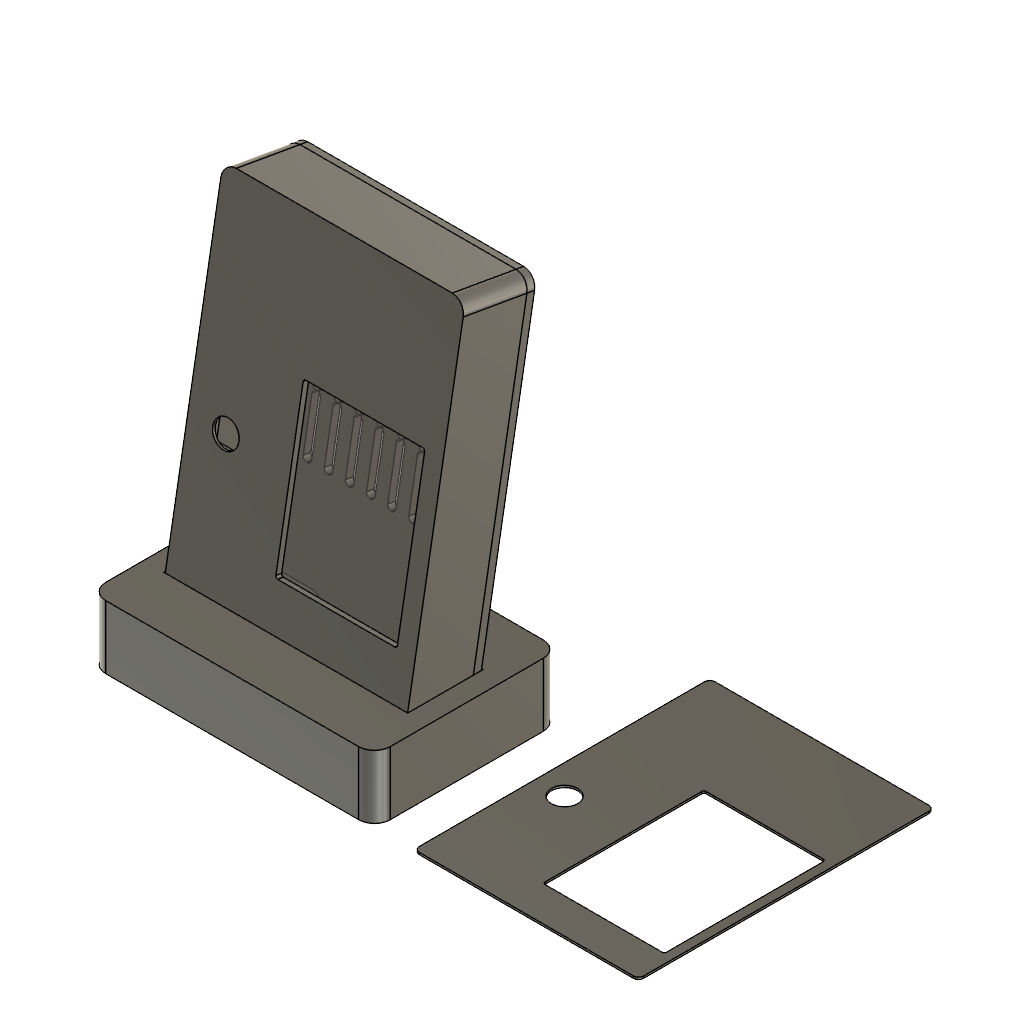
smart-picture-frame (Autodesk Fusion 360 design; units mm, degrees)
Autodesk Fusion 360 part; units mm, degrees
sketch "Shell outline" plane through (0, 0, 0) normal (0, 0, 1) x (1, 0, 0) in component "Front shell"
  line L0 (5, 0) -> (86.8, 0)
  arc A0 (86.8, 0) -> (91.8, 5) centre (86.8, 5) ccw
  line L1 (91.8, 5) -> (91.8, 134.3)
  arc A1 (91.8, 134.3) -> (86.8, 139.3) centre (86.8, 134.3) ccw
  line L2 (86.8, 139.3) -> (5, 139.3)
  arc A2 (5, 139.3) -> (0, 134.3) centre (5, 134.3) ccw
  line L3 (0, 134.3) -> (0, 5)
  arc A3 (0, 5) -> (5, 0) centre (5, 5) ccw
extrude "Shell outline (1)" add sketch "Shell outline" along normal blind 24.5 from surface at 3 makes body 1 in component "Front shell"
sketch "Cavity (leaves screw bosses)" plane through (0, 0, 0) normal (0, 0, 1) x (1, 0, 0) in component "Front shell"
  line L0 (5, 2.4) -> (86.8, 2.4)
  arc A0 (86.8, 2.4) -> (89.4, 5) centre (86.8, 5) ccw
  line L1 (89.4, 5) -> (89.4, 134.3)
  arc A1 (89.4, 134.3) -> (86.8, 136.9) centre (86.8, 134.3) ccw
  line L2 (86.8, 136.9) -> (5, 136.9)
  arc A2 (5, 136.9) -> (2.4, 134.3) centre (5, 134.3) ccw
  line L3 (2.4, 134.3) -> (2.4, 5)
  arc A3 (2.4, 5) -> (5, 2.4) centre (5, 5) ccw
  circle A4 centre (40.4, 5.4) radius 4
  circle A5 centre (86.4, 5.4) radius 4
  circle A6 centre (5.4, 133.9) radius 4
  circle A7 centre (86.4, 133.9) radius 4
extrude "Cavity (leaves screw bosses) (1)" cut sketch "Cavity (leaves screw bosses)" along normal blind 21.52 from surface at 2.98 contours L0 L1 L2 L3 A3 A4 A5 A6 A7 bodies 1 in component "Front shell"
sketch "Screen window" plane through (0, 0, 0) normal (0, 0, 1) x (1, 0, 0) in component "Front shell"
  line L0 (39.7, 29.7) -> (84.1, 29.7)
  arc A0 (84.1, 29.7) -> (84.9, 30.5) centre (84.1, 30.5) ccw
  line L1 (84.9, 30.5) -> (84.9, 89.9)
  arc A1 (84.9, 89.9) -> (84.1, 90.7) centre (84.1, 89.9) ccw
  line L2 (84.1, 90.7) -> (39.7, 90.7)
  arc A2 (39.7, 90.7) -> (38.9, 89.9) centre (39.7, 89.9) ccw
  line L3 (38.9, 89.9) -> (38.9, 30.5)
  arc A3 (38.9, 30.5) -> (39.7, 29.7) centre (39.7, 30.5) ccw
extrude "Screen window (1)" cut sketch "Screen window" along normal blind 3.04 from surface at 24.48 bodies 1 in component "Front shell"
sketch "Window inside relief" plane through (0, 0, 0) normal (0, 0, 1) x (1, 0, 0) in component "Front shell"
  line L0 (38.7, 28.7) -> (85.1, 28.7)
  arc A0 (85.1, 28.7) -> (85.9, 29.5) centre (85.1, 29.5) ccw
  line L1 (85.9, 29.5) -> (85.9, 90.9)
  arc A1 (85.9, 90.9) -> (85.1, 91.7) centre (85.1, 90.9) ccw
  line L2 (85.1, 91.7) -> (38.7, 91.7)
  arc A2 (38.7, 91.7) -> (37.9, 90.9) centre (38.7, 90.9) ccw
  line L3 (37.9, 90.9) -> (37.9, 29.5)
  arc A3 (37.9, 29.5) -> (38.7, 28.7) centre (38.7, 29.5) ccw
extrude "Window inside relief (1)" cut sketch "Window inside relief" along normal blind 0.8 from surface at 24.5 bodies 1 in component "Front shell"
sketch "Camera hole" plane through (0, 0, 0) normal (0, 0, 1) x (1, 0, 0) in component "Front shell"
  circle A0 centre (14.4, 62.4) radius 5
extrude "Camera hole (1)" cut sketch "Camera hole" along normal blind 3.04 from surface at 24.48 bodies 1 in component "Front shell"
sketch "Camera holder relief" plane through (0, 0, 0) normal (0, 0, 1) x (1, 0, 0) in component "Front shell"
  line L0 (8.9, 56.9) -> (19.9, 56.9)
  line L1 (19.9, 56.9) -> (19.9, 67.9)
  line L2 (19.9, 67.9) -> (8.9, 67.9)
  line L3 (8.9, 67.9) -> (8.9, 56.9)
extrude "Camera holder relief (1)" cut sketch "Camera holder relief" along normal blind 2.02 from surface at 24.48 bodies 1 in component "Front shell"
sketch "Screw pilot holes" plane through (0, 0, 0) normal (0, 0, 1) x (1, 0, 0) in component "Front shell"
  circle A0 centre (40.4, 5.4) radius 1.35
  circle A1 centre (86.4, 5.4) radius 1.35
  circle A2 centre (5.4, 133.9) radius 1.35
  circle A3 centre (86.4, 133.9) radius 1.35
extrude "Screw pilot holes (1)" cut sketch "Screw pilot holes" along normal blind 12.02 from surface at 2.98 bodies 1 in component "Front shell"
sketch "Cover plate" plane through (0, 0, 0) normal (0, 0, 1) x (1, 0, 0) in component "Rear cover"
  line L0 (5, 0) -> (86.8, 0)
  arc A0 (86.8, 0) -> (91.8, 5) centre (86.8, 5) ccw
  line L1 (91.8, 5) -> (91.8, 134.3)
  arc A1 (91.8, 134.3) -> (86.8, 139.3) centre (86.8, 134.3) ccw
  line L2 (86.8, 139.3) -> (5, 139.3)
  arc A2 (5, 139.3) -> (0, 134.3) centre (5, 134.3) ccw
  line L3 (0, 134.3) -> (0, 5)
  arc A3 (0, 5) -> (5, 0) centre (5, 5) ccw
extrude "Cover plate (1)" add sketch "Cover plate" along normal blind 3 separate body makes body 2 in component "Rear cover"
sketch "Locating tongue" plane through (0, 0, 0) normal (0, 0, 1) x (1, 0, 0) in component "Rear cover"
  line L0 (5, 2.75) -> (86.8, 2.75)
  arc A0 (86.8, 2.75) -> (89.05, 5) centre (86.8, 5) ccw
  line L1 (89.05, 5) -> (89.05, 134.3)
  arc A1 (89.05, 134.3) -> (86.8, 136.55) centre (86.8, 134.3) ccw
  line L2 (86.8, 136.55) -> (5, 136.55)
  arc A2 (5, 136.55) -> (2.75, 134.3) centre (5, 134.3) ccw
  line L3 (2.75, 134.3) -> (2.75, 5)
  arc A3 (2.75, 5) -> (5, 2.75) centre (5, 5) ccw
  line L4 (5, 4.35) -> (86.8, 4.35)
  arc A4 (86.8, 4.35) -> (87.45, 5) centre (86.8, 5) ccw
  line L5 (87.45, 5) -> (87.45, 134.3)
  arc A5 (87.45, 134.3) -> (86.8, 134.95) centre (86.8, 134.3) ccw
  line L6 (86.8, 134.95) -> (5, 134.95)
  arc A6 (5, 134.95) -> (4.35, 134.3) centre (5, 134.3) ccw
  line L7 (4.35, 134.3) -> (4.35, 5)
  arc A7 (4.35, 5) -> (5, 4.35) centre (5, 5) ccw
extrude "Locating tongue (1)" add sketch "Locating tongue" along normal blind 2.02 from surface at 2.98 bodies 2 in component "Rear cover"
sketch "Tongue clearance at bosses" plane through (0, 0, 0) normal (0, 0, 1) x (1, 0, 0) in component "Rear cover"
  circle A0 centre (40.4, 5.4) radius 4.4
  circle A1 centre (86.4, 5.4) radius 4.4
  circle A2 centre (5.4, 133.9) radius 4.4
  circle A3 centre (86.4, 133.9) radius 4.4
extrude "Tongue clearance at bosses (1)" cut sketch "Tongue clearance at bosses" along normal blind 2.02 from surface at 3 bodies 2 in component "Rear cover"
sketch "Rear support pads" plane through (0, 0, 0) normal (0, 0, 1) x (1, 0, 0) in component "Rear cover"
  line L0 (5.4, 17.4) -> (9.4, 17.4)
  arc A0 (9.4, 17.4) -> (10.4, 18.4) centre (9.4, 18.4) ccw
  line L1 (10.4, 18.4) -> (10.4, 22.4)
  arc A1 (10.4, 22.4) -> (9.4, 23.4) centre (9.4, 22.4) ccw
  line L2 (9.4, 23.4) -> (5.4, 23.4)
  arc A2 (5.4, 23.4) -> (4.4, 22.4) centre (5.4, 22.4) ccw
  line L3 (4.4, 22.4) -> (4.4, 18.4)
  arc A3 (4.4, 18.4) -> (5.4, 17.4) centre (5.4, 18.4) ccw
  line L4 (82.4, 17.4) -> (86.4, 17.4)
  arc A4 (86.4, 17.4) -> (87.4, 18.4) centre (86.4, 18.4) ccw
  line L5 (87.4, 18.4) -> (87.4, 22.4)
  arc A5 (87.4, 22.4) -> (86.4, 23.4) centre (86.4, 22.4) ccw
  line L6 (86.4, 23.4) -> (82.4, 23.4)
  arc A6 (82.4, 23.4) -> (81.4, 22.4) centre (82.4, 22.4) ccw
  line L7 (81.4, 22.4) -> (81.4, 18.4)
  arc A7 (81.4, 18.4) -> (82.4, 17.4) centre (82.4, 18.4) ccw
  line L8 (5.4, 121.4) -> (9.4, 121.4)
  arc A8 (9.4, 121.4) -> (10.4, 122.4) centre (9.4, 122.4) ccw
  line L9 (10.4, 122.4) -> (10.4, 126.4)
  arc A9 (10.4, 126.4) -> (9.4, 127.4) centre (9.4, 126.4) ccw
  line L10 (9.4, 127.4) -> (5.4, 127.4)
  arc A10 (5.4, 127.4) -> (4.4, 126.4) centre (5.4, 126.4) ccw
  line L11 (4.4, 126.4) -> (4.4, 122.4)
  arc A11 (4.4, 122.4) -> (5.4, 121.4) centre (5.4, 122.4) ccw
  line L12 (82.4, 121.4) -> (86.4, 121.4)
  arc A12 (86.4, 121.4) -> (87.4, 122.4) centre (86.4, 122.4) ccw
  line L13 (87.4, 122.4) -> (87.4, 126.4)
  arc A13 (87.4, 126.4) -> (86.4, 127.4) centre (86.4, 126.4) ccw
  line L14 (86.4, 127.4) -> (82.4, 127.4)
  arc A14 (82.4, 127.4) -> (81.4, 126.4) centre (82.4, 126.4) ccw
  line L15 (81.4, 126.4) -> (81.4, 122.4)
  arc A15 (81.4, 122.4) -> (82.4, 121.4) centre (82.4, 122.4) ccw
extrude "Rear support pads (1)" add sketch "Rear support pads" along normal blind 3.32 from surface at 2.98 bodies 2 in component "Rear cover"
sketch "USB cable bay" plane through (0, 0, 0) normal (0, 0, 1) x (1, 0, 0) in component "Rear cover"
  line L0 (7.4, 3.4) -> (31.4, 3.4)
  arc A0 (31.4, 3.4) -> (34.4, 6.4) centre (31.4, 6.4) ccw
  line L1 (34.4, 6.4) -> (34.4, 12.4)
  arc A1 (34.4, 12.4) -> (31.4, 15.4) centre (31.4, 12.4) ccw
  line L2 (31.4, 15.4) -> (7.4, 15.4)
  arc A2 (7.4, 15.4) -> (4.4, 12.4) centre (7.4, 12.4) ccw
  line L3 (4.4, 12.4) -> (4.4, 6.4)
  arc A3 (4.4, 6.4) -> (7.4, 3.4) centre (7.4, 6.4) ccw
extrude "USB cable bay (1)" cut sketch "USB cable bay" along normal blind 7 from surface at -1 bodies 2 in component "Rear cover"
sketch "Vent slots" plane through (0, 0, 0) normal (0, 0, 1) x (1, 0, 0) in component "Rear cover"
  line L0 (14.9, 50.4) -> (15.1, 50.4)
  arc A0 (15.1, 50.4) -> (16.6, 51.9) centre (15.1, 51.9) ccw
  line L1 (16.6, 51.9) -> (16.6, 70.9)
  arc A1 (16.6, 70.9) -> (15.1, 72.4) centre (15.1, 70.9) ccw
  line L2 (15.1, 72.4) -> (14.9, 72.4)
  arc A2 (14.9, 72.4) -> (13.4, 70.9) centre (14.9, 70.9) ccw
  line L3 (13.4, 70.9) -> (13.4, 51.9)
  arc A3 (13.4, 51.9) -> (14.9, 50.4) centre (14.9, 51.9) ccw
  line L4 (22.9, 50.4) -> (23.1, 50.4)
  arc A4 (23.1, 50.4) -> (24.6, 51.9) centre (23.1, 51.9) ccw
  line L5 (24.6, 51.9) -> (24.6, 70.9)
  arc A5 (24.6, 70.9) -> (23.1, 72.4) centre (23.1, 70.9) ccw
  line L6 (23.1, 72.4) -> (22.9, 72.4)
  arc A6 (22.9, 72.4) -> (21.4, 70.9) centre (22.9, 70.9) ccw
  line L7 (21.4, 70.9) -> (21.4, 51.9)
  arc A7 (21.4, 51.9) -> (22.9, 50.4) centre (22.9, 51.9) ccw
  line L8 (30.9, 50.4) -> (31.1, 50.4)
  arc A8 (31.1, 50.4) -> (32.6, 51.9) centre (31.1, 51.9) ccw
  line L9 (32.6, 51.9) -> (32.6, 70.9)
  arc A9 (32.6, 70.9) -> (31.1, 72.4) centre (31.1, 70.9) ccw
  line L10 (31.1, 72.4) -> (30.9, 72.4)
  arc A10 (30.9, 72.4) -> (29.4, 70.9) centre (30.9, 70.9) ccw
  line L11 (29.4, 70.9) -> (29.4, 51.9)
  arc A11 (29.4, 51.9) -> (30.9, 50.4) centre (30.9, 51.9) ccw
  line L12 (38.9, 50.4) -> (39.1, 50.4)
  arc A12 (39.1, 50.4) -> (40.6, 51.9) centre (39.1, 51.9) ccw
  line L13 (40.6, 51.9) -> (40.6, 70.9)
  arc A13 (40.6, 70.9) -> (39.1, 72.4) centre (39.1, 70.9) ccw
  line L14 (39.1, 72.4) -> (38.9, 72.4)
  arc A14 (38.9, 72.4) -> (37.4, 70.9) centre (38.9, 70.9) ccw
  line L15 (37.4, 70.9) -> (37.4, 51.9)
  arc A15 (37.4, 51.9) -> (38.9, 50.4) centre (38.9, 51.9) ccw
  line L16 (46.9, 50.4) -> (47.1, 50.4)
  arc A16 (47.1, 50.4) -> (48.6, 51.9) centre (47.1, 51.9) ccw
  line L17 (48.6, 51.9) -> (48.6, 70.9)
  arc A17 (48.6, 70.9) -> (47.1, 72.4) centre (47.1, 70.9) ccw
  line L18 (47.1, 72.4) -> (46.9, 72.4)
  arc A18 (46.9, 72.4) -> (45.4, 70.9) centre (46.9, 70.9) ccw
  line L19 (45.4, 70.9) -> (45.4, 51.9)
  arc A19 (45.4, 51.9) -> (46.9, 50.4) centre (46.9, 51.9) ccw
  line L20 (54.9, 50.4) -> (55.1, 50.4)
  arc A20 (55.1, 50.4) -> (56.6, 51.9) centre (55.1, 51.9) ccw
  line L21 (56.6, 51.9) -> (56.6, 70.9)
  arc A21 (56.6, 70.9) -> (55.1, 72.4) centre (55.1, 70.9) ccw
  line L22 (55.1, 72.4) -> (54.9, 72.4)
  arc A22 (54.9, 72.4) -> (53.4, 70.9) centre (54.9, 70.9) ccw
  line L23 (53.4, 70.9) -> (53.4, 51.9)
  arc A23 (53.4, 51.9) -> (54.9, 50.4) centre (54.9, 51.9) ccw
  line L24 (62.9, 50.4) -> (63.1, 50.4)
  arc A24 (63.1, 50.4) -> (64.6, 51.9) centre (63.1, 51.9) ccw
  line L25 (64.6, 51.9) -> (64.6, 70.9)
  arc A25 (64.6, 70.9) -> (63.1, 72.4) centre (63.1, 70.9) ccw
  line L26 (63.1, 72.4) -> (62.9, 72.4)
  arc A26 (62.9, 72.4) -> (61.4, 70.9) centre (62.9, 70.9) ccw
  line L27 (61.4, 70.9) -> (61.4, 51.9)
  arc A27 (61.4, 51.9) -> (62.9, 50.4) centre (62.9, 51.9) ccw
  line L28 (70.9, 50.4) -> (71.1, 50.4)
  arc A28 (71.1, 50.4) -> (72.6, 51.9) centre (71.1, 51.9) ccw
  line L29 (72.6, 51.9) -> (72.6, 70.9)
  arc A29 (72.6, 70.9) -> (71.1, 72.4) centre (71.1, 70.9) ccw
  line L30 (71.1, 72.4) -> (70.9, 72.4)
  arc A30 (70.9, 72.4) -> (69.4, 70.9) centre (70.9, 70.9) ccw
  line L31 (69.4, 70.9) -> (69.4, 51.9)
  arc A31 (69.4, 51.9) -> (70.9, 50.4) centre (70.9, 51.9) ccw
  line L32 (14.9, 72.4) -> (15.1, 72.4)
  arc A32 (15.1, 72.4) -> (16.6, 73.9) centre (15.1, 73.9) ccw
  line L33 (16.6, 73.9) -> (16.6, 92.9)
  arc A33 (16.6, 92.9) -> (15.1, 94.4) centre (15.1, 92.9) ccw
  line L34 (15.1, 94.4) -> (14.9, 94.4)
  arc A34 (14.9, 94.4) -> (13.4, 92.9) centre (14.9, 92.9) ccw
  line L35 (13.4, 92.9) -> (13.4, 73.9)
  arc A35 (13.4, 73.9) -> (14.9, 72.4) centre (14.9, 73.9) ccw
  line L36 (22.9, 72.4) -> (23.1, 72.4)
  arc A36 (23.1, 72.4) -> (24.6, 73.9) centre (23.1, 73.9) ccw
  line L37 (24.6, 73.9) -> (24.6, 92.9)
  arc A37 (24.6, 92.9) -> (23.1, 94.4) centre (23.1, 92.9) ccw
  line L38 (23.1, 94.4) -> (22.9, 94.4)
  arc A38 (22.9, 94.4) -> (21.4, 92.9) centre (22.9, 92.9) ccw
  line L39 (21.4, 92.9) -> (21.4, 73.9)
  arc A39 (21.4, 73.9) -> (22.9, 72.4) centre (22.9, 73.9) ccw
  line L40 (30.9, 72.4) -> (31.1, 72.4)
  arc A40 (31.1, 72.4) -> (32.6, 73.9) centre (31.1, 73.9) ccw
  line L41 (32.6, 73.9) -> (32.6, 92.9)
  arc A41 (32.6, 92.9) -> (31.1, 94.4) centre (31.1, 92.9) ccw
  line L42 (31.1, 94.4) -> (30.9, 94.4)
  arc A42 (30.9, 94.4) -> (29.4, 92.9) centre (30.9, 92.9) ccw
  line L43 (29.4, 92.9) -> (29.4, 73.9)
  arc A43 (29.4, 73.9) -> (30.9, 72.4) centre (30.9, 73.9) ccw
  line L44 (38.9, 72.4) -> (39.1, 72.4)
  arc A44 (39.1, 72.4) -> (40.6, 73.9) centre (39.1, 73.9) ccw
  line L45 (40.6, 73.9) -> (40.6, 92.9)
  arc A45 (40.6, 92.9) -> (39.1, 94.4) centre (39.1, 92.9) ccw
  line L46 (39.1, 94.4) -> (38.9, 94.4)
  arc A46 (38.9, 94.4) -> (37.4, 92.9) centre (38.9, 92.9) ccw
  line L47 (37.4, 92.9) -> (37.4, 73.9)
  arc A47 (37.4, 73.9) -> (38.9, 72.4) centre (38.9, 73.9) ccw
  line L48 (46.9, 72.4) -> (47.1, 72.4)
  arc A48 (47.1, 72.4) -> (48.6, 73.9) centre (47.1, 73.9) ccw
  line L49 (48.6, 73.9) -> (48.6, 92.9)
  arc A49 (48.6, 92.9) -> (47.1, 94.4) centre (47.1, 92.9) ccw
  line L50 (47.1, 94.4) -> (46.9, 94.4)
  arc A50 (46.9, 94.4) -> (45.4, 92.9) centre (46.9, 92.9) ccw
  line L51 (45.4, 92.9) -> (45.4, 73.9)
  arc A51 (45.4, 73.9) -> (46.9, 72.4) centre (46.9, 73.9) ccw
  line L52 (54.9, 72.4) -> (55.1, 72.4)
  arc A52 (55.1, 72.4) -> (56.6, 73.9) centre (55.1, 73.9) ccw
  line L53 (56.6, 73.9) -> (56.6, 92.9)
  arc A53 (56.6, 92.9) -> (55.1, 94.4) centre (55.1, 92.9) ccw
  line L54 (55.1, 94.4) -> (54.9, 94.4)
  arc A54 (54.9, 94.4) -> (53.4, 92.9) centre (54.9, 92.9) ccw
  line L55 (53.4, 92.9) -> (53.4, 73.9)
  arc A55 (53.4, 73.9) -> (54.9, 72.4) centre (54.9, 73.9) ccw
  line L56 (62.9, 72.4) -> (63.1, 72.4)
  arc A56 (63.1, 72.4) -> (64.6, 73.9) centre (63.1, 73.9) ccw
  line L57 (64.6, 73.9) -> (64.6, 92.9)
  arc A57 (64.6, 92.9) -> (63.1, 94.4) centre (63.1, 92.9) ccw
  line L58 (63.1, 94.4) -> (62.9, 94.4)
  arc A58 (62.9, 94.4) -> (61.4, 92.9) centre (62.9, 92.9) ccw
  line L59 (61.4, 92.9) -> (61.4, 73.9)
  arc A59 (61.4, 73.9) -> (62.9, 72.4) centre (62.9, 73.9) ccw
  line L60 (70.9, 72.4) -> (71.1, 72.4)
  arc A60 (71.1, 72.4) -> (72.6, 73.9) centre (71.1, 73.9) ccw
  line L61 (72.6, 73.9) -> (72.6, 92.9)
  arc A61 (72.6, 92.9) -> (71.1, 94.4) centre (71.1, 92.9) ccw
  line L62 (71.1, 94.4) -> (70.9, 94.4)
  arc A62 (70.9, 94.4) -> (69.4, 92.9) centre (70.9, 92.9) ccw
  line L63 (69.4, 92.9) -> (69.4, 73.9)
  arc A63 (69.4, 73.9) -> (70.9, 72.4) centre (70.9, 73.9) ccw
extrude "Vent slots (1)" cut sketch "Vent slots" along normal blind 7 from surface at -1 bodies 2 in component "Rear cover"
sketch "Screw clearance holes" plane through (0, 0, 0) normal (0, 0, 1) x (1, 0, 0) in component "Rear cover"
  circle A0 centre (40.4, 5.4) radius 1.7
  circle A1 centre (86.4, 5.4) radius 1.7
  circle A2 centre (5.4, 133.9) radius 1.7
  circle A3 centre (86.4, 133.9) radius 1.7
extrude "Screw clearance holes (1)" cut sketch "Screw clearance holes" along normal blind 7 from surface at -1 bodies 2 in component "Rear cover"
sketch "Screw head recesses" plane through (0, 0, 0) normal (0, 0, 1) x (1, 0, 0) in component "Rear cover"
  circle A0 centre (40.4, 5.4) radius 3.2
  circle A1 centre (86.4, 5.4) radius 3.2
  circle A2 centre (5.4, 133.9) radius 3.2
  circle A3 centre (86.4, 133.9) radius 3.2
extrude "Screw head recesses (1)" cut sketch "Screw head recesses" along normal blind 2.2 from surface at -1 bodies 2 in component "Rear cover"
sketch "Kit envelope 85 x 112 x 16" plane through (0, 0, 0) normal (0, 0, 1) x (1, 0, 0) in component "Kit envelope (reference)"
  line L0 (3.4, 16.4) -> (88.4, 16.4)
  line L1 (88.4, 16.4) -> (88.4, 128.4)
  line L2 (88.4, 128.4) -> (3.4, 128.4)
  line L3 (3.4, 128.4) -> (3.4, 16.4)
extrude "Kit envelope 85 x 112 x 16 (1)" add sketch "Kit envelope 85 x 112 x 16" along normal blind 16 from surface at 7.3 separate body makes body 3 in component "Kit envelope (reference)"
sketch "Stand block" plane through (0, 0, 0) normal (0, 0, 1) x (1, 0, 0) in component "Desk stand"
  line L0 (-47.9, 0) -> (47.9, 0)
  arc A0 (47.9, 0) -> (53.9, 6) centre (47.9, 6) ccw
  line L1 (53.9, 6) -> (53.9, 64)
  arc A1 (53.9, 64) -> (47.9, 70) centre (47.9, 64) ccw
  line L2 (47.9, 70) -> (-47.9, 70)
  arc A2 (-47.9, 70) -> (-53.9, 64) centre (-47.9, 64) ccw
  line L3 (-53.9, 64) -> (-53.9, 6)
  arc A3 (-53.9, 6) -> (-47.9, 0) centre (-47.9, 6) ccw
extrude "Stand block (1)" add sketch "Stand block" along normal blind 24 separate body makes body 4 in component "Desk stand"
sketch "Tilted slot profile" plane through (0, 0, 0) normal (1, 0, 0) x (0, 0, -1) in component "Desk stand"
  line L0 (-10.8795, 18) -> (-6, 45.6731)
  line L1 (-6, 45.6731) -> (-65.0885, 56.092)
  line L2 (-65.0885, 56.092) -> (-69.968, 28.4189)
  line L3 (-69.968, 28.4189) -> (-10.8795, 18)
extrude "Tilted slot" cut sketch "Tilted slot profile" along normal mid plane 92.4 bodies 4 in component "Desk stand"
sketch "Cable notch" plane through (0, 0, 0) normal (0, 0, 1) x (1, 0, 0) in component "Desk stand"
  line L0 (-43.8, 33.455) -> (-9.8, 33.455)
  line L1 (-9.8, 33.455) -> (-9.8, 72)
  line L2 (-9.8, 72) -> (-43.8, 72)
  line L3 (-43.8, 72) -> (-43.8, 33.455)
extrude "Cable notch (1)" cut sketch "Cable notch" along normal blind 19 from surface at 6 bodies 4 in component "Desk stand"
sketch "Gauge plate" plane through (0, 0, 0) normal (0, 0, 1) x (1, 0, 0) in component "Alignment gauge"
  line L0 (2, 0) -> (83, 0)
  arc A0 (83, 0) -> (85, 2) centre (83, 2) ccw
  line L1 (85, 2) -> (85, 110)
  arc A1 (85, 110) -> (83, 112) centre (83, 110) ccw
  line L2 (83, 112) -> (2, 112)
  arc A2 (2, 112) -> (0, 110) centre (2, 110) ccw
  line L3 (0, 110) -> (0, 2)
  arc A3 (0, 2) -> (2, 0) centre (2, 2) ccw
extrude "Gauge plate (1)" add sketch "Gauge plate" along normal blind 0.8 separate body makes body 5 in component "Alignment gauge"
sketch "Gauge window" plane through (0, 0, 0) normal (0, 0, 1) x (1, 0, 0) in component "Alignment gauge"
  line L0 (36.3, 13.3) -> (80.7, 13.3)
  arc A0 (80.7, 13.3) -> (81.5, 14.1) centre (80.7, 14.1) ccw
  line L1 (81.5, 14.1) -> (81.5, 73.5)
  arc A1 (81.5, 73.5) -> (80.7, 74.3) centre (80.7, 73.5) ccw
  line L2 (80.7, 74.3) -> (36.3, 74.3)
  arc A2 (36.3, 74.3) -> (35.5, 73.5) centre (36.3, 73.5) ccw
  line L3 (35.5, 73.5) -> (35.5, 14.1)
  arc A3 (35.5, 14.1) -> (36.3, 13.3) centre (36.3, 14.1) ccw
extrude "Gauge window (1)" cut sketch "Gauge window" along normal blind 0.84 from surface at -0.02 bodies 5 in component "Alignment gauge"
sketch "Gauge camera hole" plane through (0, 0, 0) normal (0, 0, 1) x (1, 0, 0) in component "Alignment gauge"
  circle A0 centre (11, 46) radius 5
extrude "Gauge camera hole (1)" cut sketch "Gauge camera hole" along normal blind 0.84 from surface at -0.02 bodies 5 in component "Alignment gauge"
component "Picture frame case" placed x (1, 0, 0) y (0, 0.173648, 0.984808) z (0, -0.984808, 0.173648) at (-45.9, 45.3777, 6.0521)
component "Desk stand" placed x (1, 0, 0) y (0, 1, 0) z (0, 0, 1) at (0, 0, 0)
component "Alignment gauge" placed x (1, 0, 0) y (0, 1, 0) z (0, 0, 1) at (68.9, 0, 0)
component "Front shell" placed x (1, 0, 0) y (0, 1, 0) z (0, 0, 1) at (0, 0, 0) in component "Picture frame case"
component "Rear cover" placed x (1, 0, 0) y (0, 1, 0) z (0, 0, 1) at (0, 0, 0) in component "Picture frame case"
component "Kit envelope (reference)" placed x (1, 0, 0) y (0, 1, 0) z (0, 0, 1) at (0, 0, 0) in component "Picture frame case"
equation "kit_width = 85.00 mm" comment "Freenove FNK0086 assembled kit (manufacturer)"
equation "kit_height = 112.00 mm" comment "Freenove FNK0086 assembled kit (manufacturer)"
equation "kit_depth = 16.00 mm" comment "Freenove FNK0086 assembled kit (manufacturer)"
equation "wall = 2.40 mm" comment "Side wall thickness"
equation "front_thickness = 3.00 mm" comment "Front face thickness"
equation "shell_depth = 24.50 mm" comment "Front shell depth (without cover)"
equation "lid_thickness = 3.00 mm" comment "Rear cover plate thickness"
equation "side_clearance = 1.00 mm" comment "Gap between kit and side walls"
equation "bottom_band = 14.00 mm" comment "Band under the kit: USB plug + 2 screws"
equation "top_band = 8.50 mm" comment "Band above the kit: 2 screws"
equation "window_width = 46.00 mm" comment "Screen window"
equation "window_height = 61.00 mm" comment "Screen window"
equation "screen_center_x = 58.50 mm" comment "Active screen centre from kit left (measured)"
equation "screen_center_y = 43.80 mm" comment "Active screen centre from kit bottom (measured)"
equation "camera_center_x = 11.00 mm" comment "OV2640 lens centre from kit left (fitted on the first print)"
equation "camera_center_y = 46.00 mm" comment "OV2640 lens centre from kit bottom (estimated from photo, confirmed by print)"
equation "camera_hole_diameter = 10.00 mm" comment "Through-hole for the lens barrel"
equation "stand_angle = 573.0 deg" comment "Desk stand lean"
equation "stand_depth = 70.00 mm" comment "Desk stand front-to-back"
equation "stand_height = 24.00 mm" comment "Desk stand height"
equation "case_width = 91.80 mm" comment "Derived outer width"
equation "case_height = 139.30 mm" comment "Derived outer height"
equation "case_depth = 27.50 mm" comment "Derived outer depth"
equation "d25 = shell_depth"
equation "d45 = lid_thickness"
equation "d69 = kit_depth"
equation "d71 = stand_height"
named bodies: "Front shell", "Rear cover", "Kit envelope (reference)", "Desk stand", "Alignment gauge"
